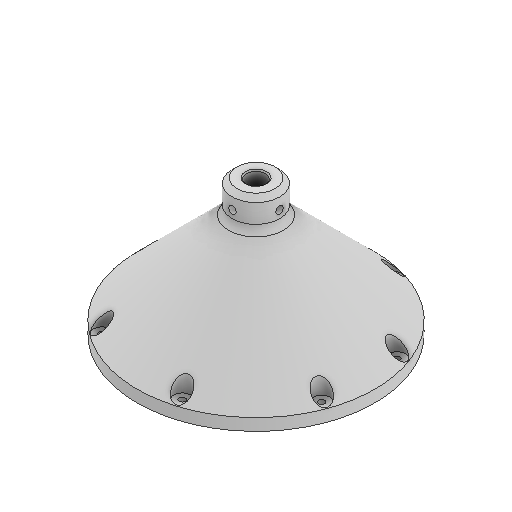
# Autodesk Inventor part: 3DP_PLA_A_Axis_Bearing_Base_Tripod_Mount
Saved by Autodesk Inventor 2027 (Build 310192060, 192F)
## iProperties
Created: 2026-01-18
Part Number: 3DP_PLA_A_Axis_Bearing_Base_Tripod_Mount
Material: Generic
Document SubType Name: Modeling
Designer: Andrzej
Density: 1 g/cm^3
Appearance: Default
Author: Andrzej
Autodesk Inventor part; units mm, degrees
ref_plane "XZ Plane" through (0, 0, 0) normal (0, 1, 0) x (-1, 0, 0)
sketch "Sketch1" plane through (0, 0, 0) normal (0, 1, 0) x (-1, 0, 0)
  circle A0 centre (0, 0) radius 100
  dimension "d0" = 200
  constraints: 1 centre point, 1 coincident
  measures "d0" diameter of A0
extrude "Extrusion1" add sketch "Sketch1" along normal blind 90
chamfer "Chamfer1" distance 80 angle 45 1 edges at (100, 90, 0)
sketch "Sketch2" plane through (0, 90, 0) normal (0, 1, 0) x (1, 0, 0)
  circle A0 centre (0, 0) radius 20 projected
  circle A1 centre (0, 0) radius 8
  circle A2 centre (0, 0) radius 4
  dimension "d6" = 16
  dimension "d7" = 40
  dimension "d10" = 8
  constraints: 2 centre point, 2 coincident
  measures "d6" diameter of A1
  measures "d7" diameter of A0
  measures "d10" diameter of A2
extrude "Extrusion2" add sketch "Sketch2" along normal blind 24 contours A0
extrude "Extrusion3" cut sketch "Sketch2" against normal blind 10 contours A2
ref_plane "Work Plane1" through (0, 10, 0) normal (0, -1, 0) x (1, 0, 0)
sketch "Sketch3" plane through (0, 10, 0) normal (0, -1, 0) x (1, 0, 0)
  point P0 (0, 0)
  point P1 (-92.5, 0)
  point P2 (-55.2372, -74.1964)
  point P3 (26.5293, -88.614)
  point P4 (86.9216, -31.6369)
  point P5 (-55.2372, 74.1964)
  point P6 (26.5293, 88.614)
  point P7 (86.9216, 31.6369)
  dimension "d14" = 92.5
  dimension "d17" = 160
  dimension "d21" = 160
  constraints: 8 other
  measures "d14" distance of point (0, 0) point (-92.5, 0)
hole "Hole1" at (-92.5, 10, 0) at (-55.2372, 10, 74.1964) at (26.5293, 10, 88.614) at (86.9216, 10, 31.6369) at (86.9216, 10, -31.6369) at (26.5293, 10, -88.614) at (-55.2372, 10, -74.1964) direction (0, 1, 0) diameter 5.2 end through all both
hole "Hole2" at (86.9216, 10, 31.6369) at (26.5293, 10, 88.614) at (-55.2372, 10, 74.1964) at (-92.5, 10, 0) at (-55.2372, 10, -74.1964) at (26.5293, 10, -88.614) at (86.9216, 10, -31.6369) direction (0, 1, 0) diameter 14 end through all
chamfer "Chamfer2" distance 4 angle 45 1 edges at (-20, 114, 0)
chamfer "Chamfer3" distance 1 angle 45 1 edges at (-8, 114, 0)
ref_plane "Work Plane2" through (20, 90, 0) normal (1, 0, 0) x (0, 1, 0)
sketch "Sketch4" plane through (20, 90, 0) normal (1, 0, 0) x (0, 1, 0)
  line L0 (0, 20) -> (20, 20) projected
  line L1 (24, 16) -> (24, -16) projected
  line L2 (0, -20) -> (20, -20) projected
  line L3 (20, -20) -> (24, -16) projected
  line L4 (20, 20) -> (24, 16) projected
  point P0 (-90, 0)
  point P1 (10.5, 0)
  dimension "d43" = 13.5
  measures "d43" distance from line of L1 point (10.5, 0)
hole "Hole3" at (20, 100.5, 0) direction (-1, 0, 0) diameter 5.5 depth 15 tip angle 118
hole "Hole4" at (20, 100.5, 0) direction (-1, 0, 0) diameter 6.2 depth 8.3
pattern_circular "Circular Pattern1" count 4 over 360 about axis through (0, 90, 0) along (0, 1, 0) of "Hole3", "Hole4"
fillet "Fillet1" radius 10 2 edges at (0, 90, -20) (0, 90, 20)
body "Solid1"
